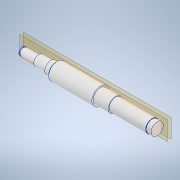
# Autodesk Inventor part: 1.1_5_Shaft_C
Saved by Autodesk Inventor 2021 (Build 250183000, 183)
## iProperties
Created: 2025-11-13
Part Number: 1.1_5_Shaft_C
Material: Aluminum 6061
Document SubType Name: Modeling
Designer: Admin
Density: 2.7 g/cm^3
Appearance: Aluminum - Flat
Mass: 148.356 g
Surface Area: 119.852 cm^2
Volume: 54.9468 cm^3
Author: Admin
Autodesk Inventor part; units mm, degrees
ref_plane "YZ Plane" through (0, 0, 0) normal (1, 0, 0) x (0, 1, 0)
ref_plane "XZ Plane" through (0, 0, 0) normal (0, 1, 0) x (-1, 0, 0)
sketch "Sketch1" plane through (0, 0, 0) normal (0, 1, 0) x (-1, 0, 0)
  line L0 (0, -14.4) -> (0, 2.4) projected
  line L1 (50, 0) -> (50, -5)
  line L2 (50, -5) -> (49.4, -5)
  line L3 (49.4, -5) -> (49.4, -4.8)
  line L4 (49.4, -4.8) -> (48.3, -4.8)
  line L5 (48.3, -4.8) -> (48.3, -5)
  line L6 (48.3, -5) -> (27.3, -5)
  line L7 (27.3, -5) -> (27.3, -7)
  line L8 (27.3, -7) -> (10.3, -7)
  line L9 (10.3, -7) -> (10.3, -8.5)
  line L10 (10.3, -8.5) -> (3.3, -8.5)
  line L11 (-58.7, -12) -> (-58.7, -10)
  line L12 (-58.7, -10) -> (-79.7, -10)
  line L13 (-79.7, -10) -> (-79.7, -9)
  line L14 (-79.7, -9) -> (-130.7, -9)
  line L15 (-130.7, -9) -> (-130.7, -8.5)
  line L16 (-130.7, -8.5) -> (-137.7, -8.5)
  line L17 (-137.7, -8.5) -> (-137.7, 0)
  line L18 (-137.7, 0) -> (50, 0)
  line L19 (87.54, 0) -> (-175.24, 0) projected
  line L20 (3.3, -10) -> (1.3, -10)
  line L21 (1.3, -10) -> (1.3, -12)
  line L22 (3.3, -10) -> (3.3, -8.5)
  line L23 (1.3, -12) -> (-58.7, -12)
  point P0 (0, 0)
  dimension "d5" = 8.5
  dimension "d6" = 0.5
  dimension "d7" = 7
  dimension "d10" = 21
  dimension "d11" = 1.1
  dimension "d12" = 0.2
  dimension "d13" = 5
  dimension "d16" = 8.5
  dimension "d18" = 17
  dimension "d19" = 10
  dimension "d21" = 21
  dimension "d22" = 7
  dimension "d23" = 2
  dimension "d24" = 134
  dimension "d25" = 60
  dimension "d26" = 0.6
  dimension "d27" = 50
  dimension "d28" = 2
  dimension "d29" = 1.5
  dimension "d30" = 2
  constraints: 44 end point, 15 perpendicular, 3 vertical, 2 horizontal, 2 point on line, 1 collinear
  measures "d5" distance between parallel lines of L18 L16
  measures "d6" distance of L14.end L15.end
  measures "d7" distance of L15.end L16.end
  measures "d10" distance of L5.end L6.end
  measures "d11" distance of L3.end L4.end
  measures "d12" distance of L2.end L3.end
  measures "d13" distance between parallel lines of L18 L6
  measures "d16" distance between parallel lines of L18 L10
  measures "d18" distance of L7.end L8.end
  measures "d19" distance between parallel lines of L18 L12
  measures "d21" distance of L11.end L12.end
  measures "d22" distance of L9.end L10.end
  measures "d23" distance of L20.start L20.end
  measures "d24" distance between parallel lines of L15 L22
  measures "d25" distance of L21.end L11.start
  measures "d26" distance of L1.end L2.end
  measures "d27" distance between parallel lines of L0 L1
  measures "d28" distance of L6.end L7.end
  measures "d29" distance between parallel lines of L20 L10
  measures "d30" distance between parallel lines of L23 L12
revolve "Revolution1" add sketch "Sketch1" angle 360 about axis through (-10, 0, 0) along (1, 0, 0)
ref_plane "Work Plane1" through (69.2, 0, -10) normal (0, 0, 1) x (1, 0, 0)
sketch "Sketch2" plane through (69.2, 0, -10) normal (0, 0, 1) x (1, 0, 0)
  line L0 (6, 0) -> (-6, 0) construction
  line L1 (6, 3) -> (-6, 3)
  line L2 (-6, -3) -> (6, -3)
  arc A0 (6, -3) -> (6, 3) centre (6, 0) ccw
  arc A1 (-6, 3) -> (-6, -3) centre (-6, 0) ccw
  line L3 (10.5, -10) -> (10.5, 10) projected
  point P0 (-69.2, 0)
  point P1 (0, 0)
  point P2 (10.5, 0)
  dimension "d31" = 6
  dimension "d32" = 10.5
  dimension "d33" = 12
  constraints: 8 end point, 4 point on circle, 4 tangent, 2 centre point, 2 midpoint, 1 horizontal, 1 parallel, 1 point on line
  measures "d31" distance between parallel lines of L1 L2
  measures "d32" distance from line of L3 point (0, 0)
  measures "d33" distance of L2.start L2.end
extrude "Extrusion1" [suppressed]
ref_plane "Work Plane2" through (-37.8, 0, -5) normal (0, 0, 1) x (1, 0, 0)
sketch "Sketch3" plane through (-37.8, 0, -5) normal (0, 0, 1) x (1, 0, 0)
  line L0 (-6.5, 0) -> (6.5, 0) construction
  line L1 (-6.5, -1.5) -> (6.5, -1.5)
  line L2 (6.5, 1.5) -> (-6.5, 1.5)
  arc A0 (-6.5, 1.5) -> (-6.5, -1.5) centre (-6.5, 0) ccw
  arc A1 (6.5, -1.5) -> (6.5, 1.5) centre (6.5, 0) ccw
  line L3 (10.5, -7) -> (10.5, 7) projected
  point P0 (37.8, 0)
  point P1 (0, 0)
  point P2 (10.5, 0)
  dimension "d36" = 3
  dimension "d37" = 13
  dimension "d38" = 10.5
  constraints: 8 end point, 4 point on circle, 4 tangent, 2 centre point, 2 midpoint, 1 horizontal, 1 parallel, 1 point on line
  measures "d36" distance between parallel lines of L2 L1
  measures "d37" distance of L0.start L0.end
  measures "d38" distance from line of L3 point (0, 0)
extrude "Extrusion2" [suppressed]
fillet "Fillet1" radius 0.2 2 edges at (-3.3, 0, 8.5) (130.7, 0, 8.5)
body "Solid1"
